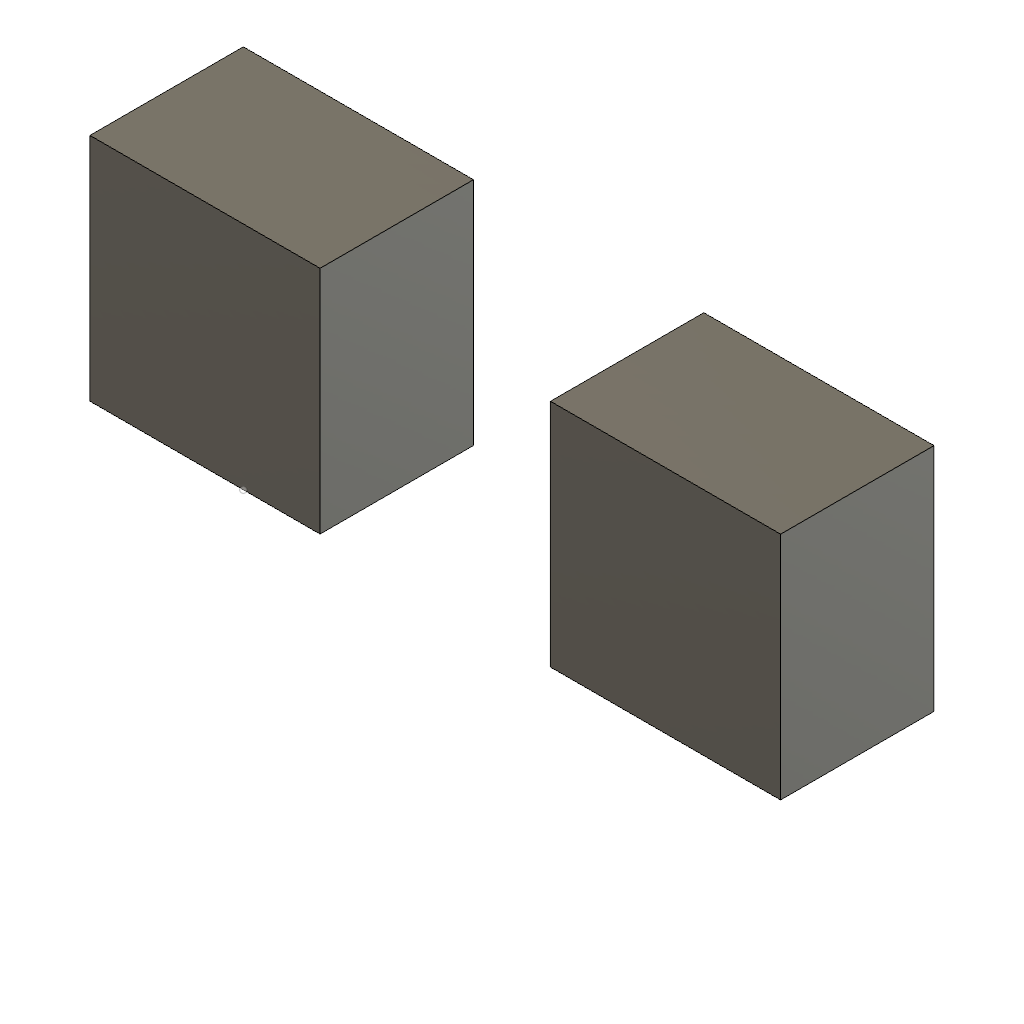
scale_two_bodies_point (Autodesk Fusion 360 design; units mm, degrees)
part number: 2026-10-20-23-25-48-087
Autodesk Fusion 360 part; units mm, degrees
sketch "BodySelectionSeedSketch1" plane through (0, 0, 0) normal (0, 0, 1) x (1, 0, 0)
  line L0 (10, 10) -> (40, 10)
  line L1 (40, 10) -> (40, 40)
  line L2 (40, 40) -> (10, 40)
  line L3 (10, 40) -> (10, 10)
extrude "BodySelectionSeed1" add sketch "BodySelectionSeedSketch1" along normal blind 20 makes body 1
sketch "BodySelectionSeedSketch2" plane through (0, 0, 0) normal (0, 0, 1) x (1, 0, 0)
  line L0 (70, 10) -> (100, 10)
  line L1 (100, 10) -> (100, 40)
  line L2 (100, 40) -> (70, 40)
  line L3 (70, 40) -> (70, 10)
extrude "BodySelectionSeed2" add sketch "BodySelectionSeedSketch2" along normal blind 20 separate body makes body 2
sketch "ScalePointSketch" plane through (0, 0, 0) normal (0, 0, 1) x (1, 0, 0)
  point P0 (10, -10)
scale "ProbeBodySelection" factor 1.4 about (10, -10, 0) bodies 1 2
named bodies: "SelectedBody1", "SelectedBody2"
